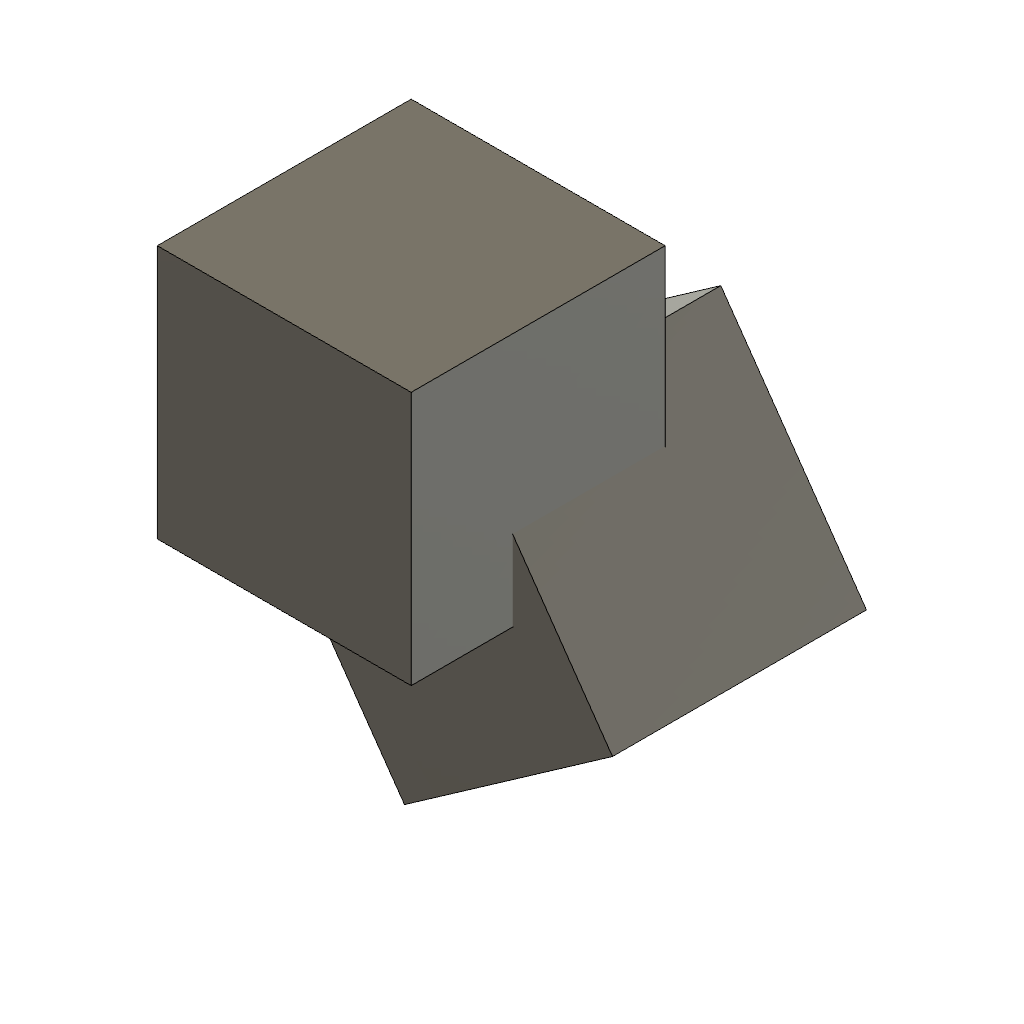
rigid_flipped (Autodesk Fusion 360 design; units mm, degrees)
part number: 2026-10-20-21-16-41-150
part number: 2026-10-20-21-16-41-347
part number: 2026-10-20-21-16-41-357
Autodesk Fusion 360 part; units mm, degrees
sketch "Sketch1" plane through (0, 0, 0) normal (0, 0, 1) x (1, 0, 0) in component "Fixed"
  line L0 (0, 0) -> (10, 0)
  line L1 (10, 0) -> (10, 10)
  line L2 (10, 10) -> (0, 10)
  line L3 (0, 10) -> (0, 0)
extrude "Extrude1" add sketch "Sketch1" along normal blind 10 makes body 1 in component "Fixed"
sketch "Sketch1 (2)" plane through (0, 0, 0) normal (0, 0, 1) x (1, 0, 0) in component "Moving"
  line L0 (0, 0) -> (10, 0)
  line L1 (10, 0) -> (10, 10)
  line L2 (10, 10) -> (0, 10)
  line L3 (0, 10) -> (0, 0)
extrude "Extrude1'" add sketch "Sketch1 (2)" along normal blind 10 separate body makes body 2 in component "Moving"
component "Fixed" placed x (1, 0, 0) y (0, 1, 0) z (0, 0, 1) at (0, 0, 0)
component "Moving" placed x (0.819152, 0.573576, 0) y (0.573576, -0.819152, 0) z (0, 0, -1) at (0, 0, 6)
